Autodesk Fusion 360 part; units mm, degrees
(part 2 of 8)
sketch "Torso panel screw | profile (1)" plane through (0, 0, 58) normal (0, 0, 1) x (1, 0, 0) in component "02 | Flat-sided NEMA23 pedestal"
  line L0 (-88.0947, -11.9) -> (-90, -10.8)
  line L1 (-90, -10.8) -> (-91.9053, -11.9)
  line L2 (-91.9053, -11.9) -> (-91.9053, -14.1)
  line L3 (-91.9053, -14.1) -> (-90, -15.2)
  line L4 (-90, -15.2) -> (-88.0947, -14.1)
  line L5 (-88.0947, -14.1) -> (-88.0947, -11.9)
  circle A0 centre (-90, -13) radius 0.9
extrude "Torso panel screw (1)" add sketch "Torso panel screw | profile (1)" along normal blind 1 separate body makes body 57 in component "02 | Flat-sided NEMA23 pedestal"
ref_plane "WorkPlane34" through (0, 0, 58) normal (0, 0, 1) x (1, 0, 0) in component "02 | Flat-sided NEMA23 pedestal"
sketch "Torso panel screw | profile (2)" plane through (0, 0, 58) normal (0, 0, 1) x (1, 0, 0) in component "02 | Flat-sided NEMA23 pedestal"
  line L0 (-38.0947, -34.9) -> (-40, -33.8)
  line L1 (-40, -33.8) -> (-41.9053, -34.9)
  line L2 (-41.9053, -34.9) -> (-41.9053, -37.1)
  line L3 (-41.9053, -37.1) -> (-40, -38.2)
  line L4 (-40, -38.2) -> (-38.0947, -37.1)
  line L5 (-38.0947, -37.1) -> (-38.0947, -34.9)
  circle A0 centre (-40, -36) radius 0.9
extrude "Torso panel screw (2)" add sketch "Torso panel screw | profile (2)" along normal blind 1 separate body makes body 58 in component "02 | Flat-sided NEMA23 pedestal"
ref_plane "WorkPlane35" through (0, 0, 58) normal (0, 0, 1) x (1, 0, 0) in component "02 | Flat-sided NEMA23 pedestal"
sketch "Torso panel screw | profile (3)" plane through (0, 0, 58) normal (0, 0, 1) x (1, 0, 0) in component "02 | Flat-sided NEMA23 pedestal"
  line L0 (-38.0947, 40.1) -> (-40, 41.2)
  line L1 (-40, 41.2) -> (-41.9053, 40.1)
  line L2 (-41.9053, 40.1) -> (-41.9053, 37.9)
  line L3 (-41.9053, 37.9) -> (-40, 36.8)
  line L4 (-40, 36.8) -> (-38.0947, 37.9)
  line L5 (-38.0947, 37.9) -> (-38.0947, 40.1)
  circle A0 centre (-40, 39) radius 0.9
extrude "Torso panel screw (3)" add sketch "Torso panel screw | profile (3)" along normal blind 1 separate body makes body 59 in component "02 | Flat-sided NEMA23 pedestal"
ref_plane "WorkPlane1" through (0, 0, -31) normal (0, 0, 1) x (1, 0, 0) in component "03 | Straight upper beam"
sketch "Straight beam sidewall -1 | profile" plane through (0, 0, -31) normal (0, 0, 1) x (1, 0, 0) in component "03 | Straight upper beam"
  line L0 (52.6, -28) -> (127.4, -28)
  line L1 (127.4, -28) -> (128, -27.4)
  line L2 (128, -27.4) -> (128, -26.1)
  line L3 (128, -26.1) -> (127.4, -25.5)
  line L4 (127.4, -25.5) -> (52.6, -25.5)
  line L5 (52.6, -25.5) -> (52, -26.1)
  line L6 (52, -26.1) -> (52, -27.4)
  line L7 (52, -27.4) -> (52.6, -28)
extrude "Straight beam sidewall -1" add sketch "Straight beam sidewall -1 | profile" along normal blind 73 separate body makes body 60 in component "03 | Straight upper beam"
ref_plane "WorkPlane2" through (0, 0, -31) normal (0, 0, 1) x (1, 0, 0) in component "03 | Straight upper beam"
sketch "Straight beam sidewall 1 | profile" plane through (0, 0, -31) normal (0, 0, 1) x (1, 0, 0) in component "03 | Straight upper beam"
  line L0 (52.6, 25.5) -> (127.4, 25.5)
  line L1 (127.4, 25.5) -> (128, 26.1)
  line L2 (128, 26.1) -> (128, 27.4)
  line L3 (128, 27.4) -> (127.4, 28)
  line L4 (127.4, 28) -> (52.6, 28)
  line L5 (52.6, 28) -> (52, 27.4)
  line L6 (52, 27.4) -> (52, 26.1)
  line L7 (52, 26.1) -> (52.6, 25.5)
extrude "Straight beam sidewall 1" add sketch "Straight beam sidewall 1 | profile" along normal blind 73 separate body makes body 61 in component "03 | Straight upper beam"
ref_plane "WorkPlane3" through (0, 0, -31) normal (0, 0, 1) x (1, 0, 0) in component "03 | Straight upper beam"
sketch "Rear removable beam panel | profile" plane through (0, 0, -31) normal (0, 0, 1) x (1, 0, 0) in component "03 | Straight upper beam"
  line L0 (55, -28) -> (125, -28)
  line L1 (125, -28) -> (128, -25)
  line L2 (128, -25) -> (128, 25)
  line L3 (128, 25) -> (125, 28)
  line L4 (125, 28) -> (55, 28)
  line L5 (55, 28) -> (52, 25)
  line L6 (52, 25) -> (52, -25)
  line L7 (52, -25) -> (55, -28)
  line L8 (68.7, -12) -> (68.725, -12.2536)
  line L9 (68.725, -12.2536) -> (68.799, -12.4975)
  line L10 (68.799, -12.4975) -> (68.9191, -12.7222)
  line L11 (68.9191, -12.7222) -> (69.0808, -12.9192)
  line L12 (69.0808, -12.9192) -> (69.2778, -13.0809)
  line L13 (69.2778, -13.0809) -> (69.5025, -13.201)
  line L14 (69.5025, -13.201) -> (69.7464, -13.275)
  line L15 (69.7464, -13.275) -> (70, -13.3)
  line L16 (70, -13.3) -> (76, -13.3)
  line L17 (76, -13.3) -> (76.2536, -13.275)
  line L18 (76.2536, -13.275) -> (76.4975, -13.201)
  line L19 (76.4975, -13.201) -> (76.7222, -13.0809)
  line L20 (76.7222, -13.0809) -> (76.9192, -12.9192)
  line L21 (76.9192, -12.9192) -> (77.0809, -12.7222)
  line L22 (77.0809, -12.7222) -> (77.201, -12.4975)
  line L23 (77.201, -12.4975) -> (77.275, -12.2536)
  line L24 (77.275, -12.2536) -> (77.3, -12)
  line L25 (77.3, -12) -> (77.275, -11.7464)
  line L26 (77.275, -11.7464) -> (77.201, -11.5025)
  line L27 (77.201, -11.5025) -> (77.0809, -11.2778)
  line L28 (77.0809, -11.2778) -> (76.9192, -11.0808)
  line L29 (76.9192, -11.0808) -> (76.7222, -10.9191)
  line L30 (76.7222, -10.9191) -> (76.4975, -10.799)
  line L31 (76.4975, -10.799) -> (76.2536, -10.725)
  line L32 (76.2536, -10.725) -> (76, -10.7)
  line L33 (76, -10.7) -> (70, -10.7)
  line L34 (70, -10.7) -> (69.7464, -10.725)
  line L35 (69.7464, -10.725) -> (69.5025, -10.799)
  line L36 (69.5025, -10.799) -> (69.2778, -10.9191)
  line L37 (69.2778, -10.9191) -> (69.0808, -11.0808)
  line L38 (69.0808, -11.0808) -> (68.9191, -11.2778)
  line L39 (68.9191, -11.2778) -> (68.799, -11.5025)
  line L40 (68.799, -11.5025) -> (68.725, -11.7464)
  line L41 (68.725, -11.7464) -> (68.7, -12)
  line L42 (68.7, 12) -> (68.725, 11.7464)
  line L43 (68.725, 11.7464) -> (68.799, 11.5025)
  line L44 (68.799, 11.5025) -> (68.9191, 11.2778)
  line L45 (68.9191, 11.2778) -> (69.0808, 11.0808)
  line L46 (69.0808, 11.0808) -> (69.2778, 10.9191)
  line L47 (69.2778, 10.9191) -> (69.5025, 10.799)
  line L48 (69.5025, 10.799) -> (69.7464, 10.725)
  line L49 (69.7464, 10.725) -> (70, 10.7)
  line L50 (70, 10.7) -> (76, 10.7)
  line L51 (76, 10.7) -> (76.2536, 10.725)
  line L52 (76.2536, 10.725) -> (76.4975, 10.799)
  line L53 (76.4975, 10.799) -> (76.7222, 10.9191)
  line L54 (76.7222, 10.9191) -> (76.9192, 11.0808)
  line L55 (76.9192, 11.0808) -> (77.0809, 11.2778)
  line L56 (77.0809, 11.2778) -> (77.201, 11.5025)
  line L57 (77.201, 11.5025) -> (77.275, 11.7464)
  line L58 (77.275, 11.7464) -> (77.3, 12)
  line L59 (77.3, 12) -> (77.275, 12.2536)
  line L60 (77.275, 12.2536) -> (77.201, 12.4975)
  line L61 (77.201, 12.4975) -> (77.0809, 12.7222)
  line L62 (77.0809, 12.7222) -> (76.9192, 12.9192)
  line L63 (76.9192, 12.9192) -> (76.7222, 13.0809)
  line L64 (76.7222, 13.0809) -> (76.4975, 13.201)
  line L65 (76.4975, 13.201) -> (76.2536, 13.275)
  line L66 (76.2536, 13.275) -> (76, 13.3)
  line L67 (76, 13.3) -> (70, 13.3)
  line L68 (70, 13.3) -> (69.7464, 13.275)
  line L69 (69.7464, 13.275) -> (69.5025, 13.201)
  line L70 (69.5025, 13.201) -> (69.2778, 13.0809)
  line L71 (69.2778, 13.0809) -> (69.0808, 12.9192)
  line L72 (69.0808, 12.9192) -> (68.9191, 12.7222)
  line L73 (68.9191, 12.7222) -> (68.799, 12.4975)
  line L74 (68.799, 12.4975) -> (68.725, 12.2536)
  line L75 (68.725, 12.2536) -> (68.7, 12)
  line L76 (77.7, -12) -> (77.725, -12.2536)
  line L77 (77.725, -12.2536) -> (77.799, -12.4975)
  line L78 (77.799, -12.4975) -> (77.9191, -12.7222)
  line L79 (77.9191, -12.7222) -> (78.0808, -12.9192)
  line L80 (78.0808, -12.9192) -> (78.2778, -13.0809)
  line L81 (78.2778, -13.0809) -> (78.5025, -13.201)
  line L82 (78.5025, -13.201) -> (78.7464, -13.275)
  line L83 (78.7464, -13.275) -> (79, -13.3)
  line L84 (79, -13.3) -> (85, -13.3)
  line L85 (85, -13.3) -> (85.2536, -13.275)
  line L86 (85.2536, -13.275) -> (85.4975, -13.201)
  line L87 (85.4975, -13.201) -> (85.7222, -13.0809)
  line L88 (85.7222, -13.0809) -> (85.9192, -12.9192)
  line L89 (85.9192, -12.9192) -> (86.0809, -12.7222)
  line L90 (86.0809, -12.7222) -> (86.201, -12.4975)
  line L91 (86.201, -12.4975) -> (86.275, -12.2536)
  line L92 (86.275, -12.2536) -> (86.3, -12)
  line L93 (86.3, -12) -> (86.275, -11.7464)
  line L94 (86.275, -11.7464) -> (86.201, -11.5025)
  line L95 (86.201, -11.5025) -> (86.0809, -11.2778)
  line L96 (86.0809, -11.2778) -> (85.9192, -11.0808)
  line L97 (85.9192, -11.0808) -> (85.7222, -10.9191)
  line L98 (85.7222, -10.9191) -> (85.4975, -10.799)
  line L99 (85.4975, -10.799) -> (85.2536, -10.725)
  line L100 (85.2536, -10.725) -> (85, -10.7)
  line L101 (85, -10.7) -> (79, -10.7)
  line L102 (79, -10.7) -> (78.7464, -10.725)
  line L103 (78.7464, -10.725) -> (78.5025, -10.799)
  line L104 (78.5025, -10.799) -> (78.2778, -10.9191)
  line L105 (78.2778, -10.9191) -> (78.0808, -11.0808)
  line L106 (78.0808, -11.0808) -> (77.9191, -11.2778)
  line L107 (77.9191, -11.2778) -> (77.799, -11.5025)
  line L108 (77.799, -11.5025) -> (77.725, -11.7464)
  line L109 (77.725, -11.7464) -> (77.7, -12)
  line L110 (77.7, 12) -> (77.725, 11.7464)
  line L111 (77.725, 11.7464) -> (77.799, 11.5025)
  line L112 (77.799, 11.5025) -> (77.9191, 11.2778)
  line L113 (77.9191, 11.2778) -> (78.0808, 11.0808)
  line L114 (78.0808, 11.0808) -> (78.2778, 10.9191)
  line L115 (78.2778, 10.9191) -> (78.5025, 10.799)
  line L116 (78.5025, 10.799) -> (78.7464, 10.725)
  line L117 (78.7464, 10.725) -> (79, 10.7)
  line L118 (79, 10.7) -> (85, 10.7)
  line L119 (85, 10.7) -> (85.2536, 10.725)
  line L120 (85.2536, 10.725) -> (85.4975, 10.799)
  line L121 (85.4975, 10.799) -> (85.7222, 10.9191)
  line L122 (85.7222, 10.9191) -> (85.9192, 11.0808)
  line L123 (85.9192, 11.0808) -> (86.0809, 11.2778)
  line L124 (86.0809, 11.2778) -> (86.201, 11.5025)
  line L125 (86.201, 11.5025) -> (86.275, 11.7464)
  line L126 (86.275, 11.7464) -> (86.3, 12)
  line L127 (86.3, 12) -> (86.275, 12.2536)
  line L128 (86.275, 12.2536) -> (86.201, 12.4975)
  line L129 (86.201, 12.4975) -> (86.0809, 12.7222)
  line L130 (86.0809, 12.7222) -> (85.9192, 12.9192)
  line L131 (85.9192, 12.9192) -> (85.7222, 13.0809)
  line L132 (85.7222, 13.0809) -> (85.4975, 13.201)
  line L133 (85.4975, 13.201) -> (85.2536, 13.275)
  line L134 (85.2536, 13.275) -> (85, 13.3)
  line L135 (85, 13.3) -> (79, 13.3)
  line L136 (79, 13.3) -> (78.7464, 13.275)
  line L137 (78.7464, 13.275) -> (78.5025, 13.201)
  line L138 (78.5025, 13.201) -> (78.2778, 13.0809)
  line L139 (78.2778, 13.0809) -> (78.0808, 12.9192)
  line L140 (78.0808, 12.9192) -> (77.9191, 12.7222)
  line L141 (77.9191, 12.7222) -> (77.799, 12.4975)
  line L142 (77.799, 12.4975) -> (77.725, 12.2536)
  line L143 (77.725, 12.2536) -> (77.7, 12)
  line L144 (86.7, -12) -> (86.725, -12.2536)
  line L145 (86.725, -12.2536) -> (86.799, -12.4975)
  line L146 (86.799, -12.4975) -> (86.9191, -12.7222)
  line L147 (86.9191, -12.7222) -> (87.0808, -12.9192)
  line L148 (87.0808, -12.9192) -> (87.2778, -13.0809)
  line L149 (87.2778, -13.0809) -> (87.5025, -13.201)
  line L150 (87.5025, -13.201) -> (87.7464, -13.275)
  line L151 (87.7464, -13.275) -> (88, -13.3)
  line L152 (88, -13.3) -> (94, -13.3)
  line L153 (94, -13.3) -> (94.2536, -13.275)
  line L154 (94.2536, -13.275) -> (94.4975, -13.201)
  line L155 (94.4975, -13.201) -> (94.7222, -13.0809)
  line L156 (94.7222, -13.0809) -> (94.9192, -12.9192)
  line L157 (94.9192, -12.9192) -> (95.0809, -12.7222)
  line L158 (95.0809, -12.7222) -> (95.201, -12.4975)
  line L159 (95.201, -12.4975) -> (95.275, -12.2536)
  line L160 (95.275, -12.2536) -> (95.3, -12)
  line L161 (95.3, -12) -> (95.275, -11.7464)
  line L162 (95.275, -11.7464) -> (95.201, -11.5025)
  line L163 (95.201, -11.5025) -> (95.0809, -11.2778)
  line L164 (95.0809, -11.2778) -> (94.9192, -11.0808)
  line L165 (94.9192, -11.0808) -> (94.7222, -10.9191)
  line L166 (94.7222, -10.9191) -> (94.4975, -10.799)
  line L167 (94.4975, -10.799) -> (94.2536, -10.725)
  line L168 (94.2536, -10.725) -> (94, -10.7)
  line L169 (94, -10.7) -> (88, -10.7)
  line L170 (88, -10.7) -> (87.7464, -10.725)
  line L171 (87.7464, -10.725) -> (87.5025, -10.799)
  line L172 (87.5025, -10.799) -> (87.2778, -10.9191)
  line L173 (87.2778, -10.9191) -> (87.0808, -11.0808)
  line L174 (87.0808, -11.0808) -> (86.9191, -11.2778)
  line L175 (86.9191, -11.2778) -> (86.799, -11.5025)
  line L176 (86.799, -11.5025) -> (86.725, -11.7464)
  line L177 (86.725, -11.7464) -> (86.7, -12)
  line L178 (86.7, 12) -> (86.725, 11.7464)
  line L179 (86.725, 11.7464) -> (86.799, 11.5025)
  line L180 (86.799, 11.5025) -> (86.9191, 11.2778)
  line L181 (86.9191, 11.2778) -> (87.0808, 11.0808)
  line L182 (87.0808, 11.0808) -> (87.2778, 10.9191)
  line L183 (87.2778, 10.9191) -> (87.5025, 10.799)
  line L184 (87.5025, 10.799) -> (87.7464, 10.725)
  line L185 (87.7464, 10.725) -> (88, 10.7)
  line L186 (88, 10.7) -> (94, 10.7)
  line L187 (94, 10.7) -> (94.2536, 10.725)
  line L188 (94.2536, 10.725) -> (94.4975, 10.799)
  line L189 (94.4975, 10.799) -> (94.7222, 10.9191)
  line L190 (94.7222, 10.9191) -> (94.9192, 11.0808)
  line L191 (94.9192, 11.0808) -> (95.0809, 11.2778)
  line L192 (95.0809, 11.2778) -> (95.201, 11.5025)
  line L193 (95.201, 11.5025) -> (95.275, 11.7464)
  line L194 (95.275, 11.7464) -> (95.3, 12)
  line L195 (95.3, 12) -> (95.275, 12.2536)
  line L196 (95.275, 12.2536) -> (95.201, 12.4975)
  line L197 (95.201, 12.4975) -> (95.0809, 12.7222)
  line L198 (95.0809, 12.7222) -> (94.9192, 12.9192)
  line L199 (94.9192, 12.9192) -> (94.7222, 13.0809)
  line L200 (94.7222, 13.0809) -> (94.4975, 13.201)
  line L201 (94.4975, 13.201) -> (94.2536, 13.275)
  line L202 (94.2536, 13.275) -> (94, 13.3)
  line L203 (94, 13.3) -> (88, 13.3)
  line L204 (88, 13.3) -> (87.7464, 13.275)
  line L205 (87.7464, 13.275) -> (87.5025, 13.201)
  line L206 (87.5025, 13.201) -> (87.2778, 13.0809)
  line L207 (87.2778, 13.0809) -> (87.0808, 12.9192)
  line L208 (87.0808, 12.9192) -> (86.9191, 12.7222)
  line L209 (86.9191, 12.7222) -> (86.799, 12.4975)
  line L210 (86.799, 12.4975) -> (86.725, 12.2536)
  line L211 (86.725, 12.2536) -> (86.7, 12)
extrude "Rear removable beam panel" add sketch "Rear removable beam panel | profile" along normal blind 2.5 separate body makes body 62 in component "03 | Straight upper beam"
ref_plane "WorkPlane4" through (0, 0, 39.5) normal (0, 0, 1) x (1, 0, 0) in component "03 | Straight upper beam"
sketch "Front removable beam panel | profile" plane through (0, 0, 39.5) normal (0, 0, 1) x (1, 0, 0) in component "03 | Straight upper beam"
  line L0 (55, -28) -> (125, -28)
  line L1 (125, -28) -> (128, -25)
  line L2 (128, -25) -> (128, 25)
  line L3 (128, 25) -> (125, 28)
  line L4 (125, 28) -> (55, 28)
  line L5 (55, 28) -> (52, 25)
  line L6 (52, 25) -> (52, -25)
  line L7 (52, -25) -> (55, -28)
extrude "Front removable beam panel" add sketch "Front removable beam panel | profile" along normal blind 2.5 separate body makes body 63 in component "03 | Straight upper beam"
ref_plane "WorkPlane5" through (0, 0, 14) normal (0, 0, 1) x (1, 0, 0) in component "03 | Straight upper beam"
sketch "Motor mount | metal, stock and holes to finalize | profile (3)" plane through (0, 0, 14) normal (0, 0, 1) x (1, 0, 0) in component "03 | Straight upper beam"
  line L0 (59.35, -23.65) -> (104.65, -23.65)
  line L1 (104.65, -23.65) -> (105.65, -22.65)
  line L2 (105.65, -22.65) -> (105.65, 22.65)
  line L3 (105.65, 22.65) -> (104.65, 23.65)
  line L4 (104.65, 23.65) -> (59.35, 23.65)
  line L5 (59.35, 23.65) -> (58.35, 22.65)
  line L6 (58.35, 22.65) -> (58.35, -22.65)
  line L7 (58.35, -22.65) -> (59.35, -23.65)
  circle A0 centre (82, 0) radius 11.2
  circle A1 centre (66.5, -15.5) radius 1.6
  circle A2 centre (66.5, 15.5) radius 1.6
  circle A3 centre (97.5, -15.5) radius 1.6
  circle A4 centre (97.5, 15.5) radius 1.6
extrude "Motor mount | metal, stock and holes to finalize''" add sketch "Motor mount | metal, stock and holes to finalize | profile (3)" along normal blind 3 separate body makes body 64 in component "03 | Straight upper beam"
ref_plane "WorkPlane6" through (0, 0, -36) normal (0, 0, 1) x (1, 0, 0) in component "03 | Straight upper beam"
sketch "Proximal bearing cheek | profile" plane through (0, 0, -36) normal (0, 0, 1) x (1, 0, 0) in component "03 | Straight upper beam"
  line L0 (-51, 0) -> (-50.5637, -6.6568)
  line L1 (-50.5637, -6.6568) -> (-49.2622, -13.1998)
  line L2 (-49.2622, -13.1998) -> (-47.1179, -19.5169)
  line L3 (-47.1179, -19.5169) -> (-44.1673, -25.5)
  line L4 (-44.1673, -25.5) -> (-40.461, -31.0468)
  line L5 (-40.461, -31.0468) -> (-36.0624, -36.0624)
  line L6 (-36.0624, -36.0624) -> (-31.0468, -40.461)
  line L7 (-31.0468, -40.461) -> (-25.5, -44.1673)
  line L8 (-25.5, -44.1673) -> (-19.5169, -47.1179)
  line L9 (-19.5169, -47.1179) -> (-13.1998, -49.2622)
  line L10 (-13.1998, -49.2622) -> (-6.6568, -50.5637)
  line L11 (-6.6568, -50.5637) -> (0, -51)
  line L12 (0, -51) -> (6.6568, -50.5637)
  line L13 (6.6568, -50.5637) -> (13.1998, -49.2622)
  line L14 (13.1998, -49.2622) -> (19.5169, -47.1179)
  line L15 (19.5169, -47.1179) -> (69, -23)
  line L16 (69, -23) -> (69, 23)
  line L17 (69, 23) -> (19.5169, 47.1179)
  line L18 (19.5169, 47.1179) -> (13.1998, 49.2622)
  line L19 (13.1998, 49.2622) -> (6.6568, 50.5637)
  line L20 (6.6568, 50.5637) -> (0, 51)
  line L21 (0, 51) -> (-6.6568, 50.5637)
  line L22 (-6.6568, 50.5637) -> (-13.1998, 49.2622)
  line L23 (-13.1998, 49.2622) -> (-19.5169, 47.1179)
  line L24 (-19.5169, 47.1179) -> (-25.5, 44.1673)
  line L25 (-25.5, 44.1673) -> (-31.0468, 40.461)
  line L26 (-31.0468, 40.461) -> (-36.0624, 36.0624)
  line L27 (-36.0624, 36.0624) -> (-40.461, 31.0468)
  line L28 (-40.461, 31.0468) -> (-44.1673, 25.5)
  line L29 (-44.1673, 25.5) -> (-47.1179, 19.5169)
  line L30 (-47.1179, 19.5169) -> (-49.2622, 13.1998)
  line L31 (-49.2622, 13.1998) -> (-50.5637, 6.6568)
  line L32 (-50.5637, 6.6568) -> (-51, 0)
  circle A0 centre (0, 0) radius 15.15
extrude "Proximal bearing cheek" add sketch "Proximal bearing cheek | profile" along normal blind 5 separate body makes body 65 in component "03 | Straight upper beam"
ref_plane "WorkPlane7" through (0, 0, 42) normal (0, 0, 1) x (1, 0, 0) in component "03 | Straight upper beam"
sketch "Proximal bearing cheek | profile (1)" plane through (0, 0, 42) normal (0, 0, 1) x (1, 0, 0) in component "03 | Straight upper beam"
  line L0 (-51, 0) -> (-50.5637, -6.6568)
  line L1 (-50.5637, -6.6568) -> (-49.2622, -13.1998)
  line L2 (-49.2622, -13.1998) -> (-47.1179, -19.5169)
  line L3 (-47.1179, -19.5169) -> (-44.1673, -25.5)
  line L4 (-44.1673, -25.5) -> (-40.461, -31.0468)
  line L5 (-40.461, -31.0468) -> (-36.0624, -36.0624)
  line L6 (-36.0624, -36.0624) -> (-31.0468, -40.461)
  line L7 (-31.0468, -40.461) -> (-25.5, -44.1673)
  line L8 (-25.5, -44.1673) -> (-19.5169, -47.1179)
  line L9 (-19.5169, -47.1179) -> (-13.1998, -49.2622)
  line L10 (-13.1998, -49.2622) -> (-6.6568, -50.5637)
  line L11 (-6.6568, -50.5637) -> (0, -51)
  line L12 (0, -51) -> (6.6568, -50.5637)
  line L13 (6.6568, -50.5637) -> (13.1998, -49.2622)
  line L14 (13.1998, -49.2622) -> (19.5169, -47.1179)
  line L15 (19.5169, -47.1179) -> (69, -23)
  line L16 (69, -23) -> (69, 23)
  line L17 (69, 23) -> (19.5169, 47.1179)
  line L18 (19.5169, 47.1179) -> (13.1998, 49.2622)
  line L19 (13.1998, 49.2622) -> (6.6568, 50.5637)
  line L20 (6.6568, 50.5637) -> (0, 51)
  line L21 (0, 51) -> (-6.6568, 50.5637)
  line L22 (-6.6568, 50.5637) -> (-13.1998, 49.2622)
  line L23 (-13.1998, 49.2622) -> (-19.5169, 47.1179)
  line L24 (-19.5169, 47.1179) -> (-25.5, 44.1673)
  line L25 (-25.5, 44.1673) -> (-31.0468, 40.461)
  line L26 (-31.0468, 40.461) -> (-36.0624, 36.0624)
  line L27 (-36.0624, 36.0624) -> (-40.461, 31.0468)
  line L28 (-40.461, 31.0468) -> (-44.1673, 25.5)
  line L29 (-44.1673, 25.5) -> (-47.1179, 19.5169)
  line L30 (-47.1179, 19.5169) -> (-49.2622, 13.1998)
  line L31 (-49.2622, 13.1998) -> (-50.5637, 6.6568)
  line L32 (-50.5637, 6.6568) -> (-51, 0)
  circle A0 centre (0, 0) radius 15.15
extrude "Proximal bearing cheek (1)" add sketch "Proximal bearing cheek | profile (1)" along normal blind 5 separate body makes body 66 in component "03 | Straight upper beam"
ref_plane "WorkPlane8" through (0, 0, 20) normal (0, 0, 1) x (1, 0, 0) in component "03 | Straight upper beam"
sketch "20T pulley envelope | tooth profile pending | profile (3)" plane through (0, 0, 20) normal (0, 0, 1) x (1, 0, 0) in component "03 | Straight upper beam"
  circle A0 centre (82, 0) radius 6.9662
  circle A1 centre (82, 0) radius 2.5
extrude "20T pulley envelope | tooth profile pending''" add sketch "20T pulley envelope | tooth profile pending | profile (3)" along normal blind 6 separate body makes body 67 in component "03 | Straight upper beam"
ref_plane "WorkPlane9" through (0, 0, 26) normal (0, 0, 1) x (1, 0, 0) in component "03 | Straight upper beam"
sketch "20T flange | profile (3)" plane through (0, 0, 26) normal (0, 0, 1) x (1, 0, 0) in component "03 | Straight upper beam"
  circle A0 centre (82, 0) radius 7.3662
  circle A1 centre (82, 0) radius 2.5
extrude "20T flange''" add sketch "20T flange | profile (3)" along normal blind 0.8 separate body makes body 68 in component "03 | Straight upper beam"
ref_plane "WorkPlane10" through (0, 0, 20) normal (0, 0, 1) x (1, 0, 0) in component "03 | Straight upper beam"
sketch "20T pulley envelope | tooth profile pending | profile (1) (2)" plane through (0, 0, 20) normal (0, 0, 1) x (1, 0, 0) in component "03 | Straight upper beam"
  circle A0 centre (175, 0) radius 6.9662
  circle A1 centre (175, 0) radius 3
extrude "20T pulley envelope | tooth profile pending (1)'" add sketch "20T pulley envelope | tooth profile pending | profile (1) (2)" along normal blind 6 separate body makes body 69 in component "03 | Straight upper beam"
ref_plane "WorkPlane11" through (0, 0, 26) normal (0, 0, 1) x (1, 0, 0) in component "03 | Straight upper beam"
sketch "20T flange | profile (1) (2)" plane through (0, 0, 26) normal (0, 0, 1) x (1, 0, 0) in component "03 | Straight upper beam"
  circle A0 centre (175, 0) radius 7.3662
  circle A1 centre (175, 0) radius 3
extrude "20T flange (1)'" add sketch "20T flange | profile (1) (2)" along normal blind 0.8 separate body makes body 70 in component "03 | Straight upper beam"
ref_plane "WorkPlane12" through (0, 0, 20) normal (0, 0, 1) x (1, 0, 0) in component "03 | Straight upper beam"
sketch "Internal 1:1 span | belt length pending | profile" plane through (0, 0, 20) normal (0, 0, 1) x (1, 0, 0) in component "03 | Straight upper beam"
  line L0 (82, 7.0162) -> (175, 7.0162)
  line L1 (175, 7.0162) -> (175, 5.7162)
  line L2 (175, 5.7162) -> (82, 5.7162)
  line L3 (82, 5.7162) -> (82, 7.0162)
extrude "Internal 1:1 span | belt length pending" add sketch "Internal 1:1 span | belt length pending | profile" along normal blind 6 separate body makes body 71 in component "03 | Straight upper beam"
ref_plane "WorkPlane13" through (0, 0, 20) normal (0, 0, 1) x (1, 0, 0) in component "03 | Straight upper beam"
sketch "Internal 1:1 span | belt length pending | profile (1)" plane through (0, 0, 20) normal (0, 0, 1) x (1, 0, 0) in component "03 | Straight upper beam"
  line L0 (82, -5.7162) -> (175, -5.7162)
  line L1 (175, -5.7162) -> (175, -7.0162)
  line L2 (175, -7.0162) -> (82, -7.0162)
  line L3 (82, -7.0162) -> (82, -5.7162)
extrude "Internal 1:1 span | belt length pending (1)" add sketch "Internal 1:1 span | belt length pending | profile (1)" along normal blind 6 separate body makes body 72 in component "03 | Straight upper beam"
ref_plane "WorkPlane14" through (0, 0, 20) normal (0, 0, 1) x (1, 0, 0) in component "03 | Straight upper beam"
sketch "Internal 1:1 drive wrap | profile" plane through (0, 0, 20) normal (0, 0, 1) x (1, 0, 0) in component "03 | Straight upper beam"
  circle A0 centre (82, 0) radius 7.0162
  circle A1 centre (82, 0) radius 5.7162
extrude "Internal 1:1 drive wrap" add sketch "Internal 1:1 drive wrap | profile" along normal blind 6 separate body makes body 73 in component "03 | Straight upper beam"
ref_plane "WorkPlane15" through (0, 0, 20) normal (0, 0, 1) x (1, 0, 0) in component "03 | Straight upper beam"
sketch "Internal 1:1 driven wrap | profile" plane through (0, 0, 20) normal (0, 0, 1) x (1, 0, 0) in component "03 | Straight upper beam"
  circle A0 centre (175, 0) radius 7.0162
  circle A1 centre (175, 0) radius 5.7162
extrude "Internal 1:1 driven wrap" add sketch "Internal 1:1 driven wrap | profile" along normal blind 6 separate body makes body 74 in component "03 | Straight upper beam"
ref_plane "WorkPlane16" through (0, 0, -42) normal (0, 0, 1) x (1, 0, 0) in component "03 | Straight upper beam"
sketch "Distal flat fork cheek | profile" plane through (0, 0, -42) normal (0, 0, 1) x (1, 0, 0) in component "03 | Straight upper beam"
  line L0 (118, -23) -> (158.9273, -38.8029)
  line L1 (158.9273, -38.8029) -> (164.1296, -40.5689)
  line L2 (164.1296, -40.5689) -> (169.5179, -41.6407)
  line L3 (169.5179, -41.6407) -> (175, -42)
  line L4 (175, -42) -> (180.4821, -41.6407)
  line L5 (180.4821, -41.6407) -> (185.8704, -40.5689)
  line L6 (185.8704, -40.5689) -> (191.0727, -38.8029)
  line L7 (191.0727, -38.8029) -> (196, -36.3731)
  line L8 (196, -36.3731) -> (200.568, -33.3208)
  line L9 (200.568, -33.3208) -> (204.6985, -29.6985)
  line L10 (204.6985, -29.6985) -> (208.3208, -25.568)
  line L11 (208.3208, -25.568) -> (211.3731, -21)
  line L12 (211.3731, -21) -> (213.8029, -16.0727)
  line L13 (213.8029, -16.0727) -> (215.5689, -10.8704)
  line L14 (215.5689, -10.8704) -> (216.6407, -5.4821)
  line L15 (216.6407, -5.4821) -> (217, 0)
  line L16 (217, 0) -> (216.6407, 5.4821)
  line L17 (216.6407, 5.4821) -> (215.5689, 10.8704)
  line L18 (215.5689, 10.8704) -> (213.8029, 16.0727)
  line L19 (213.8029, 16.0727) -> (211.3731, 21)
  line L20 (211.3731, 21) -> (208.3208, 25.568)
  line L21 (208.3208, 25.568) -> (204.6985, 29.6985)
  line L22 (204.6985, 29.6985) -> (200.568, 33.3208)
  line L23 (200.568, 33.3208) -> (196, 36.3731)
  line L24 (196, 36.3731) -> (191.0727, 38.8029)
  line L25 (191.0727, 38.8029) -> (185.8704, 40.5689)
  line L26 (185.8704, 40.5689) -> (180.4821, 41.6407)
  line L27 (180.4821, 41.6407) -> (175, 42)
  line L28 (175, 42) -> (169.5179, 41.6407)
  line L29 (169.5179, 41.6407) -> (164.1296, 40.5689)
  line L30 (164.1296, 40.5689) -> (158.9273, 38.8029)
  line L31 (158.9273, 38.8029) -> (118, 23)
  line L32 (118, 23) -> (118, -23)
  circle A0 centre (175, 0) radius 15.2
extrude "Distal flat fork cheek" add sketch "Distal flat fork cheek | profile" along normal blind 5 separate body makes body 75 in component "03 | Straight upper beam"
ref_plane "WorkPlane17" through (0, 0, 48) normal (0, 0, 1) x (1, 0, 0) in component "03 | Straight upper beam"
sketch "Distal flat fork cheek | profile (1)" plane through (0, 0, 48) normal (0, 0, 1) x (1, 0, 0) in component "03 | Straight upper beam"
  line L0 (118, -23) -> (158.9273, -38.8029)
  line L1 (158.9273, -38.8029) -> (164.1296, -40.5689)
  line L2 (164.1296, -40.5689) -> (169.5179, -41.6407)
  line L3 (169.5179, -41.6407) -> (175, -42)
  line L4 (175, -42) -> (180.4821, -41.6407)
  line L5 (180.4821, -41.6407) -> (185.8704, -40.5689)
  line L6 (185.8704, -40.5689) -> (191.0727, -38.8029)
  line L7 (191.0727, -38.8029) -> (196, -36.3731)
  line L8 (196, -36.3731) -> (200.568, -33.3208)
  line L9 (200.568, -33.3208) -> (204.6985, -29.6985)
  line L10 (204.6985, -29.6985) -> (208.3208, -25.568)
  line L11 (208.3208, -25.568) -> (211.3731, -21)
  line L12 (211.3731, -21) -> (213.8029, -16.0727)
  line L13 (213.8029, -16.0727) -> (215.5689, -10.8704)
  line L14 (215.5689, -10.8704) -> (216.6407, -5.4821)
  line L15 (216.6407, -5.4821) -> (217, 0)
  line L16 (217, 0) -> (216.6407, 5.4821)
  line L17 (216.6407, 5.4821) -> (215.5689, 10.8704)
  line L18 (215.5689, 10.8704) -> (213.8029, 16.0727)
  line L19 (213.8029, 16.0727) -> (211.3731, 21)
  line L20 (211.3731, 21) -> (208.3208, 25.568)
  line L21 (208.3208, 25.568) -> (204.6985, 29.6985)
  line L22 (204.6985, 29.6985) -> (200.568, 33.3208)
  line L23 (200.568, 33.3208) -> (196, 36.3731)
  line L24 (196, 36.3731) -> (191.0727, 38.8029)
  line L25 (191.0727, 38.8029) -> (185.8704, 40.5689)
  line L26 (185.8704, 40.5689) -> (180.4821, 41.6407)
  line L27 (180.4821, 41.6407) -> (175, 42)
  line L28 (175, 42) -> (169.5179, 41.6407)
  line L29 (169.5179, 41.6407) -> (164.1296, 40.5689)
  line L30 (164.1296, 40.5689) -> (158.9273, 38.8029)
  line L31 (158.9273, 38.8029) -> (118, 23)
  line L32 (118, 23) -> (118, -23)
  circle A0 centre (175, 0) radius 15.2
extrude "Distal flat fork cheek (1)" add sketch "Distal flat fork cheek | profile (1)" along normal blind 5 separate body makes body 76 in component "03 | Straight upper beam"
ref_plane "WorkPlane18" through (0, 0, 53.3) normal (0, 0, 1) x (1, 0, 0) in component "03 | Straight upper beam"
sketch "Elbow recessed graphite seam | profile" plane through (0, 0, 53.3) normal (0, 0, 1) x (1, 0, 0) in component "03 | Straight upper beam"
  circle A0 centre (175, 0) radius 41
extrude "Elbow recessed graphite seam" add sketch "Elbow recessed graphite seam | profile" along normal blind 0.7 separate body makes body 77 in component "03 | Straight upper beam"
ref_plane "WorkPlane19" through (0, 0, 54) normal (0, 0, 1) x (1, 0, 0) in component "03 | Straight upper beam"
sketch "Elbow narrow white annulus | profile" plane through (0, 0, 54) normal (0, 0, 1) x (1, 0, 0) in component "03 | Straight upper beam"
  circle A0 centre (175, 0) radius 40.7
  circle A1 centre (175, 0) radius 39.3
extrude "Elbow narrow white annulus" add sketch "Elbow narrow white annulus | profile" along normal blind 1.3 separate body makes body 78 in component "03 | Straight upper beam"
ref_plane "WorkPlane20" through (0, 0, 54) normal (0, 0, 1) x (1, 0, 0) in component "03 | Straight upper beam"
sketch "Elbow flat Green Marble face | profile" plane through (0, 0, 54) normal (0, 0, 1) x (1, 0, 0) in component "03 | Straight upper beam"
  line L0 (214, 0) -> (213.8122, 3.8227)
  line L1 (213.8122, 3.8227) -> (213.2506, 7.6085)
  line L2 (213.2506, 7.6085) -> (212.3207, 11.3211)
  line L3 (212.3207, 11.3211) -> (211.0313, 14.9247)
  line L4 (211.0313, 14.9247) -> (209.3949, 18.3845)
  line L5 (209.3949, 18.3845) -> (207.4273, 21.6672)
  line L6 (207.4273, 21.6672) -> (205.1474, 24.7413)
  line L7 (205.1474, 24.7413) -> (202.5772, 27.5772)
  line L8 (202.5772, 27.5772) -> (199.7413, 30.1474)
  line L9 (199.7413, 30.1474) -> (196.6672, 32.4273)
  line L10 (196.6672, 32.4273) -> (193.3845, 34.3949)
  line L11 (193.3845, 34.3949) -> (189.9247, 36.0313)
  line L12 (189.9247, 36.0313) -> (186.3211, 37.3207)
  line L13 (186.3211, 37.3207) -> (182.6085, 38.2506)
  line L14 (182.6085, 38.2506) -> (178.8227, 38.8122)
  line L15 (178.8227, 38.8122) -> (175, 39)
  line L16 (175, 39) -> (171.1773, 38.8122)
  line L17 (171.1773, 38.8122) -> (167.3915, 38.2506)
  line L18 (167.3915, 38.2506) -> (163.6789, 37.3207)
  line L19 (163.6789, 37.3207) -> (160.0753, 36.0313)
  line L20 (160.0753, 36.0313) -> (156.6155, 34.3949)
  line L21 (156.6155, 34.3949) -> (153.3328, 32.4273)
  line L22 (153.3328, 32.4273) -> (150.2587, 30.1474)
  line L23 (150.2587, 30.1474) -> (147.4228, 27.5772)
  line L24 (147.4228, 27.5772) -> (144.8526, 24.7413)
  line L25 (144.8526, 24.7413) -> (142.5727, 21.6672)
  line L26 (142.5727, 21.6672) -> (140.6051, 18.3845)
  line L27 (140.6051, 18.3845) -> (138.9687, 14.9247)
  line L28 (138.9687, 14.9247) -> (137.6793, 11.3211)
  line L29 (137.6793, 11.3211) -> (136.7494, 7.6085)
  line L30 (136.7494, 7.6085) -> (136.1878, 3.8227)
  line L31 (136.1878, 3.8227) -> (136, 0)
  line L32 (136, 0) -> (136.1878, -3.8227)
  line L33 (136.1878, -3.8227) -> (136.7494, -7.6085)
  line L34 (136.7494, -7.6085) -> (137.6793, -11.3211)
  line L35 (137.6793, -11.3211) -> (138.9687, -14.9247)
  line L36 (138.9687, -14.9247) -> (140.6051, -18.3845)
  line L37 (140.6051, -18.3845) -> (142.5727, -21.6672)
  line L38 (142.5727, -21.6672) -> (144.8526, -24.7413)
  line L39 (144.8526, -24.7413) -> (147.4228, -27.5772)
  line L40 (147.4228, -27.5772) -> (150.2587, -30.1474)
  line L41 (150.2587, -30.1474) -> (153.3328, -32.4273)
  line L42 (153.3328, -32.4273) -> (156.6155, -34.3949)
  line L43 (156.6155, -34.3949) -> (160.0753, -36.0313)
  line L44 (160.0753, -36.0313) -> (163.6789, -37.3207)
  line L45 (163.6789, -37.3207) -> (167.3915, -38.2506)
  line L46 (167.3915, -38.2506) -> (171.1773, -38.8122)
  line L47 (171.1773, -38.8122) -> (175, -39)
  line L48 (175, -39) -> (178.8227, -38.8122)
  line L49 (178.8227, -38.8122) -> (182.6085, -38.2506)
  line L50 (182.6085, -38.2506) -> (186.3211, -37.3207)
  line L51 (186.3211, -37.3207) -> (189.9247, -36.0313)
  line L52 (189.9247, -36.0313) -> (193.3845, -34.3949)
  line L53 (193.3845, -34.3949) -> (196.6672, -32.4273)
  line L54 (196.6672, -32.4273) -> (199.7413, -30.1474)
  line L55 (199.7413, -30.1474) -> (202.5772, -27.5772)
  line L56 (202.5772, -27.5772) -> (205.1474, -24.7413)
  line L57 (205.1474, -24.7413) -> (207.4273, -21.6672)
  line L58 (207.4273, -21.6672) -> (209.3949, -18.3845)
  line L59 (209.3949, -18.3845) -> (211.0313, -14.9247)
  line L60 (211.0313, -14.9247) -> (212.3207, -11.3211)
  line L61 (212.3207, -11.3211) -> (213.2506, -7.6085)
  line L62 (213.2506, -7.6085) -> (213.8122, -3.8227)
  line L63 (213.8122, -3.8227) -> (214, 0)
  circle A0 centre (209, 0) radius 1.65
  circle A1 centre (192, 29.4449) radius 1.65
  circle A2 centre (158, 29.4449) radius 1.65
  circle A3 centre (141, 0) radius 1.65
  circle A4 centre (158, -29.4449) radius 1.65
  circle A5 centre (192, -29.4449) radius 1.65
extrude "Elbow flat Green Marble face" add sketch "Elbow flat Green Marble face | profile" along normal blind 1.4 separate body makes body 79 in component "03 | Straight upper beam"
ref_plane "WorkPlane21" through (0, 0, 55.45) normal (0, 0, 1) x (1, 0, 0) in component "03 | Straight upper beam"
sketch "Elbow flush M3 head | profile" plane through (0, 0, 55.45) normal (0, 0, 1) x (1, 0, 0) in component "03 | Straight upper beam"
  line L0 (210.9486, 1.125) -> (209, 2.25)
  line L1 (209, 2.25) -> (207.0514, 1.125)
  line L2 (207.0514, 1.125) -> (207.0514, -1.125)
  line L3 (207.0514, -1.125) -> (209, -2.25)
  line L4 (209, -2.25) -> (210.9486, -1.125)
  line L5 (210.9486, -1.125) -> (210.9486, 1.125)
  circle A0 centre (209, 0) radius 0.9
extrude "Elbow flush M3 head" add sketch "Elbow flush M3 head | profile" along normal blind 0.6 separate body makes body 80 in component "03 | Straight upper beam"
ref_plane "WorkPlane22" through (0, 0, 55.45) normal (0, 0, 1) x (1, 0, 0) in component "03 | Straight upper beam"
sketch "Elbow flush M3 head | profile (1)" plane through (0, 0, 55.45) normal (0, 0, 1) x (1, 0, 0) in component "03 | Straight upper beam"
  line L0 (193.9486, 30.5699) -> (192, 31.6949)
  line L1 (192, 31.6949) -> (190.0514, 30.5699)
  line L2 (190.0514, 30.5699) -> (190.0514, 28.3199)
  line L3 (190.0514, 28.3199) -> (192, 27.1949)
  line L4 (192, 27.1949) -> (193.9486, 28.3199)
  line L5 (193.9486, 28.3199) -> (193.9486, 30.5699)
  circle A0 centre (192, 29.4449) radius 0.9
extrude "Elbow flush M3 head (1)" add sketch "Elbow flush M3 head | profile (1)" along normal blind 0.6 separate body makes body 81 in component "03 | Straight upper beam"
ref_plane "WorkPlane23" through (0, 0, 55.45) normal (0, 0, 1) x (1, 0, 0) in component "03 | Straight upper beam"
sketch "Elbow flush M3 head | profile (2)" plane through (0, 0, 55.45) normal (0, 0, 1) x (1, 0, 0) in component "03 | Straight upper beam"
  line L0 (159.9486, 30.5699) -> (158, 31.6949)
  line L1 (158, 31.6949) -> (156.0514, 30.5699)
  line L2 (156.0514, 30.5699) -> (156.0514, 28.3199)
  line L3 (156.0514, 28.3199) -> (158, 27.1949)
  line L4 (158, 27.1949) -> (159.9486, 28.3199)
  line L5 (159.9486, 28.3199) -> (159.9486, 30.5699)
  circle A0 centre (158, 29.4449) radius 0.9
extrude "Elbow flush M3 head (2)" add sketch "Elbow flush M3 head | profile (2)" along normal blind 0.6 separate body makes body 82 in component "03 | Straight upper beam"
ref_plane "WorkPlane24" through (0, 0, 55.45) normal (0, 0, 1) x (1, 0, 0) in component "03 | Straight upper beam"
sketch "Elbow flush M3 head | profile (3)" plane through (0, 0, 55.45) normal (0, 0, 1) x (1, 0, 0) in component "03 | Straight upper beam"
  line L0 (142.9486, 1.125) -> (141, 2.25)
  line L1 (141, 2.25) -> (139.0514, 1.125)
  line L2 (139.0514, 1.125) -> (139.0514, -1.125)
  line L3 (139.0514, -1.125) -> (141, -2.25)
  line L4 (141, -2.25) -> (142.9486, -1.125)
  line L5 (142.9486, -1.125) -> (142.9486, 1.125)
  circle A0 centre (141, 0) radius 0.9
extrude "Elbow flush M3 head (3)" add sketch "Elbow flush M3 head | profile (3)" along normal blind 0.6 separate body makes body 83 in component "03 | Straight upper beam"
ref_plane "WorkPlane25" through (0, 0, 55.45) normal (0, 0, 1) x (1, 0, 0) in component "03 | Straight upper beam"
sketch "Elbow flush M3 head | profile (4)" plane through (0, 0, 55.45) normal (0, 0, 1) x (1, 0, 0) in component "03 | Straight upper beam"
  line L0 (159.9486, -28.3199) -> (158, -27.1949)
  line L1 (158, -27.1949) -> (156.0514, -28.3199)
  line L2 (156.0514, -28.3199) -> (156.0514, -30.5699)
  line L3 (156.0514, -30.5699) -> (158, -31.6949)
  line L4 (158, -31.6949) -> (159.9486, -30.5699)
  line L5 (159.9486, -30.5699) -> (159.9486, -28.3199)
  circle A0 centre (158, -29.4449) radius 0.9
extrude "Elbow flush M3 head (4)" add sketch "Elbow flush M3 head | profile (4)" along normal blind 0.6 separate body makes body 84 in component "03 | Straight upper beam"
ref_plane "WorkPlane26" through (0, 0, 55.45) normal (0, 0, 1) x (1, 0, 0) in component "03 | Straight upper beam"
sketch "Elbow flush M3 head | profile (5)" plane through (0, 0, 55.45) normal (0, 0, 1) x (1, 0, 0) in component "03 | Straight upper beam"
  line L0 (193.9486, -28.3199) -> (192, -27.1949)
  line L1 (192, -27.1949) -> (190.0514, -28.3199)
  line L2 (190.0514, -28.3199) -> (190.0514, -30.5699)
  line L3 (190.0514, -30.5699) -> (192, -31.6949)
  line L4 (192, -31.6949) -> (193.9486, -30.5699)
  line L5 (193.9486, -30.5699) -> (193.9486, -28.3199)
  circle A0 centre (192, -29.4449) radius 0.9
extrude "Elbow flush M3 head (5)" add sketch "Elbow flush M3 head | profile (5)" along normal blind 0.6 separate body makes body 85 in component "03 | Straight upper beam"
ref_plane "WorkPlane27" through (0, 0, 42.15) normal (0, 0, 1) x (1, 0, 0) in component "03 | Straight upper beam"
sketch "Thin white longitudinal rail | profile" plane through (0, 0, 42.15) normal (0, 0, 1) x (1, 0, 0) in component "03 | Straight upper beam"
  line L0 (56.6, -26.2) -> (123.4, -26.2)
  line L1 (123.4, -26.2) -> (124, -25.6)
  line L2 (124, -25.6) -> (124, -24.4)
  line L3 (124, -24.4) -> (123.4, -23.8)
  line L4 (123.4, -23.8) -> (56.6, -23.8)
  line L5 (56.6, -23.8) -> (56, -24.4)
  line L6 (56, -24.4) -> (56, -25.6)
  line L7 (56, -25.6) -> (56.6, -26.2)
extrude "Thin white longitudinal rail" add sketch "Thin white longitudinal rail | profile" along normal blind 1.1 separate body makes body 86 in component "03 | Straight upper beam"
ref_plane "WorkPlane28" through (0, 0, 42) normal (0, 0, 1) x (1, 0, 0) in component "03 | Straight upper beam"
sketch "Beam service fastener | profile" plane through (0, 0, 42) normal (0, 0, 1) x (1, 0, 0) in component "03 | Straight upper beam"
  line L0 (60.8187, -19.95) -> (59, -18.9)
  line L1 (59, -18.9) -> (57.1813, -19.95)
  line L2 (57.1813, -19.95) -> (57.1813, -22.05)
  line L3 (57.1813, -22.05) -> (59, -23.1)
  line L4 (59, -23.1) -> (60.8187, -22.05)
  line L5 (60.8187, -22.05) -> (60.8187, -19.95)
  circle A0 centre (59, -21) radius 0.9
extrude "Beam service fastener" add sketch "Beam service fastener | profile" along normal blind 1 separate body makes body 87 in component "03 | Straight upper beam"
ref_plane "WorkPlane29" through (0, 0, 42) normal (0, 0, 1) x (1, 0, 0) in component "03 | Straight upper beam"
sketch "Beam service fastener | profile (1)" plane through (0, 0, 42) normal (0, 0, 1) x (1, 0, 0) in component "03 | Straight upper beam"
  line L0 (60.8187, 22.05) -> (59, 23.1)
  line L1 (59, 23.1) -> (57.1813, 22.05)
  line L2 (57.1813, 22.05) -> (57.1813, 19.95)
  line L3 (57.1813, 19.95) -> (59, 18.9)
  line L4 (59, 18.9) -> (60.8187, 19.95)
  line L5 (60.8187, 19.95) -> (60.8187, 22.05)
  circle A0 centre (59, 21) radius 0.9
extrude "Beam service fastener (1)" add sketch "Beam service fastener | profile (1)" along normal blind 1 separate body makes body 88 in component "03 | Straight upper beam"
ref_plane "WorkPlane30" through (0, 0, 42) normal (0, 0, 1) x (1, 0, 0) in component "03 | Straight upper beam"
sketch "Beam service fastener | profile (2)" plane through (0, 0, 42) normal (0, 0, 1) x (1, 0, 0) in component "03 | Straight upper beam"
  line L0 (122.8187, -19.95) -> (121, -18.9)
  line L1 (121, -18.9) -> (119.1813, -19.95)
  line L2 (119.1813, -19.95) -> (119.1813, -22.05)
  line L3 (119.1813, -22.05) -> (121, -23.1)
  line L4 (121, -23.1) -> (122.8187, -22.05)
  line L5 (122.8187, -22.05) -> (122.8187, -19.95)
  circle A0 centre (121, -21) radius 0.9
extrude "Beam service fastener (2)" add sketch "Beam service fastener | profile (2)" along normal blind 1 separate body makes body 89 in component "03 | Straight upper beam"
ref_plane "WorkPlane31" through (0, 0, 42) normal (0, 0, 1) x (1, 0, 0) in component "03 | Straight upper beam"
sketch "Beam service fastener | profile (3)" plane through (0, 0, 42) normal (0, 0, 1) x (1, 0, 0) in component "03 | Straight upper beam"
  line L0 (122.8187, 22.05) -> (121, 23.1)
  line L1 (121, 23.1) -> (119.1813, 22.05)
  line L2 (119.1813, 22.05) -> (119.1813, 19.95)
  line L3 (119.1813, 19.95) -> (121, 18.9)
  line L4 (121, 18.9) -> (122.8187, 19.95)
  line L5 (122.8187, 19.95) -> (122.8187, 22.05)
  circle A0 centre (121, 21) radius 0.9
extrude "Beam service fastener (3)" add sketch "Beam service fastener | profile (3)" along normal blind 1 separate body makes body 90 in component "03 | Straight upper beam"
ref_plane "WorkPlane32" through (0, 0, -31) normal (0, 0, 1) x (1, 0, 0) in component "03 | Straight upper beam"
sketch "Output coupling sleeve | fastener detail pending | profile" plane through (0, 0, -31) normal (0, 0, 1) x (1, 0, 0) in component "03 | Straight upper beam"
  circle A0 centre (0, 0) radius 15
  circle A1 centre (0, 0) radius 9
extrude "Output coupling sleeve | fastener detail pending" add sketch "Output coupling sleeve | fastener detail pending | profile" along normal blind 7 separate body makes body 91 in component "03 | Straight upper beam"
ref_plane "WorkPlane33" through (0, 0, 24) normal (0, 0, 1) x (1, 0, 0) in component "03 | Straight upper beam"
sketch "Output coupling sleeve | fastener detail pending | profile (1)" plane through (0, 0, 24) normal (0, 0, 1) x (1, 0, 0) in component "03 | Straight upper beam"
  circle A0 centre (0, 0) radius 15
  circle A1 centre (0, 0) radius 9
extrude "Output coupling sleeve | fastener detail pending (1)" add sketch "Output coupling sleeve | fastener detail pending | profile (1)" along normal blind 23 separate body makes body 92 in component "03 | Straight upper beam"
ref_plane "WorkPlane1" through (0, 0, -31) normal (0, 0, 1) x (1, 0, 0) in component "04 | Straight forearm beam"
sketch "Straight beam sidewall -1 | profile (2)" plane through (0, 0, -31) normal (0, 0, 1) x (1, 0, 0) in component "04 | Straight forearm beam"
  line L0 (42.6, -28) -> (107.4, -28)
  line L1 (107.4, -28) -> (108, -27.4)
  line L2 (108, -27.4) -> (108, -26.1)
  line L3 (108, -26.1) -> (107.4, -25.5)
  line L4 (107.4, -25.5) -> (42.6, -25.5)
  line L5 (42.6, -25.5) -> (42, -26.1)
  line L6 (42, -26.1) -> (42, -27.4)
  line L7 (42, -27.4) -> (42.6, -28)
extrude "Straight beam sidewall -1'" add sketch "Straight beam sidewall -1 | profile (2)" along normal blind 73 separate body makes body 93 in component "04 | Straight forearm beam"
ref_plane "WorkPlane2" through (0, 0, -31) normal (0, 0, 1) x (1, 0, 0) in component "04 | Straight forearm beam"
sketch "Straight beam sidewall 1 | profile (2)" plane through (0, 0, -31) normal (0, 0, 1) x (1, 0, 0) in component "04 | Straight forearm beam"
  line L0 (42.6, 25.5) -> (107.4, 25.5)
  line L1 (107.4, 25.5) -> (108, 26.1)
  line L2 (108, 26.1) -> (108, 27.4)
  line L3 (108, 27.4) -> (107.4, 28)
  line L4 (107.4, 28) -> (42.6, 28)
  line L5 (42.6, 28) -> (42, 27.4)
  line L6 (42, 27.4) -> (42, 26.1)
  line L7 (42, 26.1) -> (42.6, 25.5)
extrude "Straight beam sidewall 1'" add sketch "Straight beam sidewall 1 | profile (2)" along normal blind 73 separate body makes body 94 in component "04 | Straight forearm beam"
ref_plane "WorkPlane3" through (0, 0, -31) normal (0, 0, 1) x (1, 0, 0) in component "04 | Straight forearm beam"